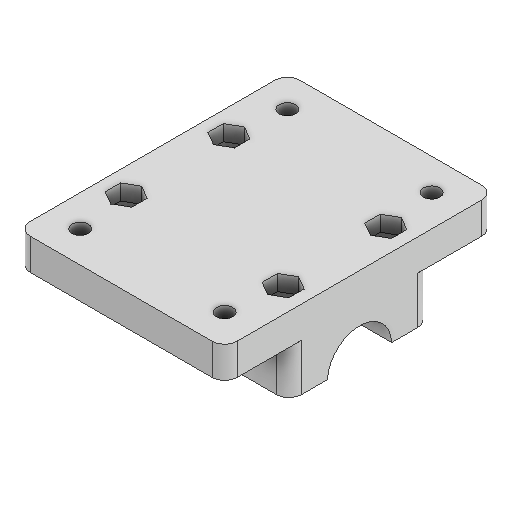
# Autodesk Inventor part: 3DP_PLA_REF_Ant_Mounting_Bracket
Saved by Autodesk Inventor 2027 (Build 310192060, 192F)
## iProperties
Created: 2026-01-18
Part Number: 3DP_PLA_REF_Ant_Mounting_Bracket
Material: Generic
Document SubType Name: Modeling
Designer: Andrzej
Density: 1 g/cm^3
Appearance: Default
Author: Andrzej
Autodesk Inventor part; units mm, degrees
ref_plane "YZ Plane" through (0, 0, 0) normal (1, 0, 0) x (0, 1, 0)
ref_plane "XZ Plane" through (0, 0, 0) normal (0, 1, 0) x (-1, 0, 0)
ref_plane "XY Plane" through (0, 0, 0) normal (0, 0, 1) x (1, 0, 0)
sketch "Sketch1" plane through (0, 0, 0) normal (0, 1, 0) x (-1, 0, 0)
  line L0 (33, 43) -> (-33, 43)
  line L1 (-33, 43) -> (-33, -43)
  line L2 (-33, -43) -> (33, -43)
  line L3 (33, -43) -> (33, 43)
  line L4 (33, 22.5) -> (-33, 22.5)
  line L5 (33, -22.5) -> (-33, -22.5)
  point P0 (0, 0)
  point P1 (23, 33)
  point P2 (23, -33)
  point P3 (-23, -33)
  point P4 (-23, 33)
  dimension "d0" = 66
  dimension "d1" = 86
  dimension "d2" = 33
  dimension "d3" = 43
  dimension "d4" = 46
  dimension "d5" = 66
  dimension "d6" = 10
  dimension "d7" = 10
  dimension "d8" = 22.5
  dimension "d9" = 22.5
  constraints: 12 end point, 4 point on line, 3 perpendicular, 2 horizontal alignment, 2 parallel, 2 vertical alignment, 1 horizontal
  measures "d0" distance of L0.start L0.end
  measures "d1" distance of L0.end L1.end
  measures "d2" distance from line of L3 point (0, 0)
  measures "d3" distance from line of L0 point (0, 0)
  measures "d4" distance of point (-23, 33) point (23, 33)
  measures "d5" distance of point (23, -33) point (23, 33)
  measures "d6" distance from line of L3 point (23, 33)
  measures "d7" distance from line of L0 point (23, 33)
  measures "d8" distance from line of point (0, 0) L4
  measures "d9" distance from line of L5 point (0, 0)
extrude "Extrusion1" add sketch "Sketch1" along normal blind 10
hole "Hole1" at (-23, 0, 33) at (-23, 0, -33) at (23, 0, -33) at (23, 0, 33) direction (0, 1, 0) diameter 5.2 end through all
extrude "Extrusion2" add sketch "Sketch1" against normal blind 15 contours L3 L5 L1 L4
sketch "Sketch2" plane through (-33, 0, 43) normal (-1, 0, 0) x (0, 0, 1)
  line L0 (-86, 0) -> (-65.5, 0) projected
  line L1 (-65.5, 0) -> (-65.5, -15) projected
  line L2 (-20.5, -15) -> (-65.5, -15) projected
  line L3 (-20.5, 0) -> (-20.5, -15) projected
  line L4 (-20.5, 0) -> (0, 0) projected
  line L5 (0, 0) -> (0, 10) projected
  line L6 (-86, 10) -> (0, 10) projected
  line L7 (-86, 0) -> (-86, 10) projected
  circle A0 centre (-43, -15.5) radius 10.25
  point P0 (-43, 0)
  dimension "d22" = 20.5
  dimension "d23" = 45
  dimension "d24" = 22.5
  dimension "d25" = 0.5
  constraints: 1 centre point
  measures "d22" diameter of A0
  measures "d23" distance of L2.start L1.end
  measures "d24" distance from line of A0.centre L3
  measures "d25" distance from line of L2 A0.centre
extrude "Extrusion3" cut sketch "Sketch2" against normal through all contours A0 L2 | L2 A0
sketch "Sketch3" plane through (0, -15, 0) normal (0, -1, 0) x (1, 0, 0)
  line L0 (-33, 10.2378) -> (33, 10.2378) projected
  line L1 (33, 10.2378) -> (33, 22.5) projected
  line L2 (33, 22.5) -> (-33, 22.5) projected
  line L3 (-33, 22.5) -> (-33, 10.2378) projected
  line L4 (33, -10.2378) -> (-33, -10.2378) projected
  line L5 (-33, -10.2378) -> (-33, -22.5) projected
  line L6 (-33, -22.5) -> (33, -22.5) projected
  line L7 (33, -22.5) -> (33, -10.2378) projected
  point P0 (0, 0)
  point P1 (25, 16.3689)
  point P2 (25, -16.3689)
  point P3 (-25, 16.3689)
  point P4 (-25, -16.3689)
  dimension "d28" = 8
  dimension "d29" = 8
  dimension "d30" = 12.2622
  dimension "d31" = 12.2622
  dimension "d32" = 6.1311
  dimension "d33" = 6.1311
  constraints: 2 vertical alignment, 1 horizontal alignment
  measures "d28" distance from line of L1 point (25, 16.369)
  measures "d29" distance from line of L3 point (-25, 16.369)
  measures "d30" distance of L2.end L0.start
  measures "d31" distance of L4.end L5.end
  measures "d32" distance from line of L2 point (-25, 16.369)
  measures "d33" distance from line of L6 point (-25, -16.369)
hole "Hole2" at (25, -15, 16.3689) at (25, -15, -16.3689) at (-25, -15, 16.3689) at (-25, -15, -16.3689) direction (0, 1, 0) diameter 5.2 end through all
sketch "Sketch4" plane through (0, 10, 0) normal (0, 1, 0) x (1, 0, 0)
  circle A0 centre (-25, -16.3689) radius 2.6 projected
  circle A1 centre (-25, 16.3689) radius 2.6 projected
  circle A2 centre (25, -16.3689) radius 2.6 projected
  line L0 (-29.25, -13.9152) -> (-25, -11.4614)
  line L1 (-25, -11.4614) -> (-20.75, -13.9152)
  line L2 (-20.75, -13.9152) -> (-20.75, -18.8226)
  line L3 (-20.75, -18.8226) -> (-25, -21.2764)
  line L4 (-25, -21.2764) -> (-29.25, -18.8226)
  line L5 (-29.25, -18.8226) -> (-29.25, -13.9152)
  line L6 (-29.25, 18.8226) -> (-25, 21.2764)
  line L7 (-25, 21.2764) -> (-20.75, 18.8226)
  line L8 (-20.75, 18.8226) -> (-20.75, 13.9152)
  line L9 (-20.75, 13.9152) -> (-25, 11.4614)
  line L10 (-25, 11.4614) -> (-29.25, 13.9152)
  line L11 (-29.25, 13.9152) -> (-29.25, 18.8226)
  line L12 (20.75, -13.9152) -> (25, -11.4614)
  line L13 (25, -11.4614) -> (29.25, -13.9152)
  line L14 (29.25, -13.9152) -> (29.25, -18.8226)
  line L15 (29.25, -18.8226) -> (25, -21.2764)
  line L16 (25, -21.2764) -> (20.75, -18.8226)
  line L17 (20.75, -18.8226) -> (20.75, -13.9152)
  circle A3 centre (-25, 16.3689) radius 2.6 projected
  circle A4 centre (-25, -16.3689) radius 2.6 projected
  circle A5 centre (25, 16.3689) radius 2.6 projected
  circle A6 centre (25, -16.3689) radius 2.6 projected
  circle A7 centre (23, -33) radius 2.6 projected
  circle A8 centre (23, 33) radius 2.6 projected
  circle A9 centre (-23, 33) radius 2.6 projected
  circle A10 centre (-23, -33) radius 2.6 projected
  line L18 (33, -43) -> (33, 43) projected
  line L19 (33, 43) -> (-33, 43) projected
  line L20 (-33, 43) -> (-33, -43) projected
  line L21 (-33, -43) -> (33, -43) projected
  line L22 (20.75, 18.8226) -> (25, 21.2764)
  line L23 (25, 21.2764) -> (29.25, 18.8226)
  line L24 (29.25, 18.8226) -> (29.25, 13.9152)
  line L25 (29.25, 13.9152) -> (25, 11.4614)
  line L26 (25, 11.4614) -> (20.75, 13.9152)
  line L27 (20.75, 13.9152) -> (20.75, 18.8226)
  line L28 (33, -43) -> (33, 43) projected
  point P0 (0, 0)
  dimension "d41" = 8.5
  dimension "d42" = 8.5
  dimension "d43" = 8.5
  dimension "d45" = 8.5
  constraints: 48 end point, 4 coincident, 4 parallel, 52 other
  measures "d41" distance between parallel lines of L2 L5
  measures "d42" distance between parallel lines of L8 L11
  measures "d43" distance between parallel lines of L14 L17
  measures "d45" distance between parallel lines of L24 L27
extrude "Extrusion4" cut sketch "Sketch4" against normal blind 5 contours L0 L1 L2 L3 L4 L5 | L6 L7 L8 L9 L10 L11 | L12 L13 L14 L15 L16 L17 | L22 L23 L24 L25 L26 L27
fillet "Fillet1" radius 4 8 edges at (-33, 5, 43) (33, 5, 43) (33, 5, -43) (-33, 5, -43) (-33, -7.5, -22.5) (33, -7.5, -22.5) (33, -7.5, 22.5) (-33, -7.5, 22.5)
equation "\"d2\" = 0.5 * d0"
equation "\"d3\" = 0.5 * d1"
equation "\"d6\" = -0.5 * d4 + 0.5 * d0"
equation "\"d7\" = -0.5 * d5 + 0.5 * d1"
equation "\"d9\" = d8"
equation "\"d24\" = 0.5 * d23"
equation "\"d29\" = d28"
equation "\"d32\" = 0.5 * d30"
equation "\"d33\" = 0.5 * d31"
equation "\"d42\" = d41"
equation "\"d43\" = d41"
equation "\"d45\" = d43"
body "Solid1"
